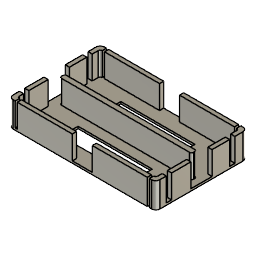
BodyWithArms (Autodesk Fusion 360 archive; units mm, degrees)
design "2SBatteryHolder"
part number: 2025-10-23-18-50-40-159
Autodesk Fusion 360 part; units mm, degrees
(part 1 of 2)
sketch "Sketch1" plane through (0, 0, 0) normal (0, 0, 1) x (1, 0, 0)
  line L0 (-32.7, -18.6) -> (-32.7, 18.6)
  line L1 (32.7, 18.6) -> (32.7, -18.6)
  line L2 (32.7, -19.6) -> (-32.7, 19.6) construction
  line L3 (-32.7, -19.6) -> (32.7, 19.6) construction
  line L4 (-29.9642, -1.4107) -> (30.45, -1.4107)
  line L5 (-29.9642, 0.9987) -> (30.45, 0.9987)
  line L6 (-34.7, -19.6) -> (-34.7, 19.6)
  line L7 (34.7, 19.6) -> (34.7, -19.6)
  arc A0 (-32.7, 21.6) -> (-34.7, 19.6) centre (-32.7, 19.6) ccw
  arc A1 (-34.7, -19.6) -> (-32.7, -21.6) centre (-32.7, -19.6) ccw
  arc A2 (32.7, -21.6) -> (34.7, -19.6) centre (32.7, -19.6) ccw
  arc A3 (34.7, 19.6) -> (32.7, 21.6) centre (32.7, 19.6) ccw
  arc A4 (32.7, 18.6) -> (31.7, 19.6) centre (31.7, 18.6) ccw
  arc A5 (-32.7, -18.6) -> (-31.7, -19.6) centre (-31.7, -18.6) ccw
  arc A6 (-31.7, 19.6) -> (-32.7, 18.6) centre (-31.7, 18.6) ccw
  arc A7 (31.7, -19.6) -> (32.7, -18.6) centre (31.7, -18.6) ccw
  line L8 (-30.9642, 0) -> (-30.95, 0)
  line L9 (-30.9642, -0.0013) -> (-30.9642, -0.4107)
  line L10 (31.45, -0.0013) -> (31.45, -0.4107)
  line L11 (-32.7366, -16.6001) -> (-34.7, -16.6001)
  line L12 (-32.7583, -14.1002) -> (-34.7, -14.1002)
  line L13 (34.6417, -14.1002) -> (32.7, -14.1002)
  line L14 (34.6634, -16.6001) -> (32.7, -16.6001)
  line L15 (-32.7583, 15.7998) -> (-34.7, 15.7998)
  line L16 (-32.7366, 13.2999) -> (-34.7, 13.2999)
  line L17 (34.6417, 15.7998) -> (32.7, 15.7998)
  line L18 (34.6634, 13.2999) -> (32.7, 13.2999)
  arc A8 (31.45, -0.0013) -> (30.45, 0.9987) centre (30.45, -0.0013) ccw
  arc A9 (30.45, -1.4107) -> (31.45, -0.4107) centre (30.45, -0.4107) ccw
  arc A10 (-29.9642, 0.9987) -> (-30.9642, -0.0013) centre (-29.9642, -0.0013) ccw
  arc A11 (-30.9642, -0.4107) -> (-29.9642, -1.4107) centre (-29.9642, -0.4107) ccw
  line L19 (-4.7, -19.6) -> (-4.7, -21.6)
  line L20 (4.7, -19.6) -> (4.7, -21.6)
  line L21 (32.7, -21.6) -> (4.7, -21.6)
  line L22 (-4.7, -21.6) -> (-32.7, -21.6)
  line L23 (31.7, -19.6) -> (4.7, -19.6)
  line L24 (-4.7, -19.6) -> (-31.7, -19.6)
  line L25 (4.7, 19.6) -> (4.7, 21.6)
  line L26 (-4.7, 19.6) -> (-4.7, 21.6)
  line L27 (-32.7, 21.6) -> (-4.7, 21.6)
  line L28 (4.7, 21.6) -> (32.7, 21.6)
  line L29 (-31.7, 19.6) -> (-4.7, 19.6)
  line L30 (4.7, 19.6) -> (31.7, 19.6)
  line L31 (-4.7, -19.6) -> (4.7, -19.6)
  line L32 (-4.7, -21.6) -> (4.7, -21.6)
  line L33 (-4.7, 21.6) -> (4.7, 21.6)
  line L34 (-4.7, 19.6) -> (4.7, 19.6)
  line L35 (17.4965, -6.1) -> (-17.5035, -6.1)
  line L36 (-17.5035, -6.1) -> (-17.5035, -14.1)
  line L37 (-17.5035, -14.1) -> (17.4965, -14.1)
  line L38 (17.4965, -14.1) -> (17.4965, -6.1)
  line L39 (17.4965, -6.1) -> (-17.5035, -14.1) construction
  line L40 (-17.5035, -6.1) -> (17.4965, -14.1) construction
  line L41 (17.4965, 6.1) -> (17.4965, 14.1)
  line L42 (17.4965, 14.1) -> (-17.5035, 6.1) construction
  line L43 (-17.5035, 6.1) -> (17.4965, 6.1)
  line L44 (-17.5035, 14.1) -> (17.4965, 6.1) construction
  line L45 (17.4965, 14.1) -> (-17.5035, 14.1)
  line L46 (-17.5035, 14.1) -> (-17.5035, 6.1)
  line L47 (32.7, 5.0447) -> (34.7, 5.0447)
  line L48 (32.7, -5) -> (34.7, -5)
  line L49 (-34.7, 5.0447) -> (-32.7, 5.0447)
  line L50 (-34.7, -5) -> (-32.7, -5)
  line L51 (-31.7, -19.6) -> (-31.7, -21.6)
  line L52 (-30.7, -19.6) -> (-30.7, -21.6)
  line L53 (-31.7, 19.6) -> (-31.7, 21.6)
  line L54 (-30.7, 21.6) -> (-30.7, 19.6)
  line L55 (31.7, 19.6) -> (31.7, 21.6)
  line L56 (30.7, 19.6) -> (30.7, 21.6)
  line L57 (31.7, -19.6) -> (31.7, -21.6)
  line L58 (31.7, -21.6) -> (30.7, -21.6)
  line L59 (30.7, -21.6) -> (30.7, -19.6)
  line L60 (-32.8064, 13.2999) -> (-32.7, 13.2999)
  line L61 (-32.7715, 15.7998) -> (-32.7, 15.7998)
  line L62 (-32.7583, -14.1002) -> (-32.7, -14.1002)
  line L63 (-34.7, -14.1002) -> (-32.7, -14.1002)
  line L64 (34.5487, -14.1002) -> (34.7, -14.1002)
  line L65 (34.5809, -16.6001) -> (34.7, -16.6001)
  line L66 (34.5908, 13.2999) -> (34.7, 13.2999)
  line L67 (34.5914, 15.7998) -> (34.7, 15.7998)
  line L68 (-34.7, -16.6001) -> (-32.7, -16.6001)
  point P0 (-0.0035, -10.1)
  point P1 (-0.0035, 10.1)
  dimension "d1" = 65.4
  dimension "d2" = 39.2
  dimension "d6" = 2
  dimension "d7" = 1
  dimension "d10" = 5
  dimension "d11" = 2.5
  dimension "d15" = 67.4
  dimension "d16" = 29.9
  dimension "d19" = 1
  dimension "d22" = 30
  dimension "d23" = 30
  dimension "d24" = 30
  dimension "d25" = 30
  dimension "d28" = 35
  dimension "d29" = 8
  dimension "d32" = 0
  dimension "d33" = 20.2
  dimension "d38" = -67.4
  dimension "d39" = 0
  constraint horizontal L23
  constraint perpendicular L0 L23
  constraint parallel L23 L29
  constraint parallel L0 L1
  constraint coincident L2 origin
  constraint coincident L3 origin
  constraint perpendicular L1 L4
  constraint perpendicular L1 L5
  constraint tangent A0 L27
  constraint tangent L6 A0
  constraint tangent A1 L21
  constraint tangent L6 A1
  constraint equal A0 A1
  constraint tangent L7 A2
  constraint tangent A2 L21
  constraint equal A0 A2
  constraint tangent A3 L27
  constraint tangent L7 A3
  constraint equal A0 A3
  constraint coincident L3.end L29
  constraint coincident L3.end L1
  constraint tangent A4 L29
  constraint tangent L1 A4
  constraint coincident L3.start L23
  constraint coincident L3.start L0
  constraint tangent A5 L23
  constraint tangent L0 A5
  constraint equal A4 A5
  constraint coincident L2.end L0
  constraint coincident L2.end L29
  constraint tangent L0 A6
  constraint tangent A6 L29
  constraint equal A4 A6
  constraint coincident L2.start L1
  constraint coincident L2.start L23
  constraint tangent L1 A7
  constraint tangent A7 L23
  constraint equal A4 A7
  constraint perpendicular L4 L9
  constraint coincident L9 L8.start
  constraint perpendicular L4 L10
  constraint coincident L6 L11.end
  constraint perpendicular L6 L11
  constraint coincident L6 L12.end
  constraint perpendicular L6 L12
  constraint tangent L5 A8
  constraint tangent L10 A8
  constraint tangent L4 A9
  constraint tangent L10 A9
  constraint equal A8 A9
  constraint tangent L5 A10
  constraint tangent L9 A10
  constraint equal A8 A10
  constraint tangent L9 A11
  constraint tangent L4 A11
  constraint equal A8 A11
  constraint coincident L19.end L21
  constraint perpendicular L19 L21
  constraint perpendicular L20 L21
  constraint collinear L21 L22
  constraint collinear L23 L24
  constraint coincident L25.end L27
  constraint perpendicular L25 L27
  constraint perpendicular L26 L27
  constraint collinear L27 L28
  constraint collinear L29 L30
  constraint perpendicular L20 L31
  constraint perpendicular L25 L34
  constraint horizontal L35
  constraint perpendicular L35 L36
  constraint parallel L35 L37
  constraint parallel L36 L38
  constraint coincident L39 P0
  constraint coincident L40 P0
  constraint coincident L1 L47.start
  constraint coincident L7 L47.end
  constraint perpendicular L7 L47
  constraint coincident L1 L48.start
  constraint coincident L7 L48.end
  constraint perpendicular L7 L48
  constraint coincident L22 L51.end
  constraint perpendicular L22 L51
  constraint coincident L24 L52.start
  constraint coincident L22 L52.end
  constraint perpendicular L22 L52
  constraint coincident L27 L53.end
  constraint perpendicular L27 L53
  constraint coincident L27 L54.start
  constraint coincident L29 L54.end
  constraint perpendicular L29 L54
  constraint coincident L28 L55.end
  constraint perpendicular L28 L55
  constraint coincident L30 L56.start
  constraint coincident L28 L56.end
  constraint perpendicular L28 L56
  constraint coincident L21 L57.end
  constraint perpendicular L21 L57
  constraint coincident L21 L58.end
  constraint coincident L23 L59.end
  constraint perpendicular L23 L59
  constraint coincident L16 L60.start
  constraint coincident L0 L60.end
  constraint perpendicular L0 L60
  constraint coincident L15 L61.start
  constraint coincident L0 L61.end
  constraint perpendicular L0 L61
  constraint coincident L0 L62.end
  constraint perpendicular L0 L62
  constraint perpendicular L0 L63
  constraint coincident L13 L64.start
  constraint coincident L7 L64.end
  constraint perpendicular L7 L64
  constraint coincident L14 L65.start
  constraint coincident L7 L65.end
  constraint perpendicular L7 L65
  constraint coincident L18 L66.start
  constraint coincident L7 L66.end
  constraint perpendicular L7 L66
  constraint coincident L17 L67.start
  constraint coincident L7 L67.end
  constraint perpendicular L7 L67
  constraint coincident L0 L68.end
  constraint perpendicular L0 L68
  measures "d1" distance of L2.end L3.end
  measures "d2" distance of L3.start L2.end
  measures "d6" radius of A0
  measures "d7" radius of A4
  measures "d10" distance of A1.end L11.start
  measures "d11" distance of L11.start L12.start
  measures "d19" radius of A8
  measures "d22" distance of L6.start L19.start
  measures "d23" distance of L7.end L20.start
  measures "d24" distance of L7.start L25.start
  measures "d25" distance of L6.end L26.start
  measures "d28" distance of L36.end L37.end
  measures "d29" distance of L35.end L36.end
extrude "Extrude1" add sketch "Sketch1" along normal blind 1 contours L0 L1 A4 A5 A6 A7 L23 L24 L29 L30 L31 L34 | L0 L6 L11 L12 L62 L63 L68 | L22 L24 L51 L52 | L0 L6 L49 L50 | L19 L20 L31 L32 | L0 L6 L15 L16 L60 L61 | L27 L29 L53 L54 | L1 L7 L13 L14 L64 L65 | L25 L26 L33 L34 | L1 L7 L47 L48 | L1 L7 L17 L18 L66 L67
extrude "Extrude2" add sketch "Sketch1" along normal blind 12 contours L0 L6 A1 A5 L11 L22 L51 L68 | L0 L6 L12 L50 L62 L63 | L19 L22 L24 L52 | L0 L6 L16 L49 L60 | L20 L21 L23 L59 | L0 L6 A0 A6 L15 L27 L53 L61 | L1 L7 A2 A7 L14 L21 L57 L65 | L26 L27 L29 L54 | L1 L7 L13 L48 L64 | L25 L28 L30 L56 | L1 L7 L18 L47 L66 | L1 L7 A3 A4 L17 L28 L55 L67 | L4 L5 L9 L10 A8 A9 A10 A11

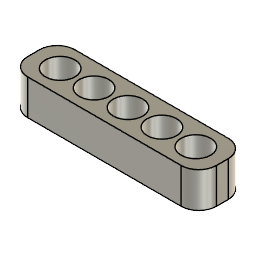
design "LedIndicator"
part number: 2025-10-29-04-20-47-498
Autodesk Fusion 360 part; units mm, degrees
sketch "Sketch1" plane through (0, 0, 0) normal (0, 0, 1) x (1, 0, 0)
  line L0 (13, 4) -> (-13, 4)
  line L1 (-16, 1) -> (-16, -1)
  line L2 (-13, -4) -> (13, -4)
  line L3 (16, -1) -> (16, 1)
  line L4 (16, 4) -> (-16, -4) construction
  line L5 (-16, 4) -> (16, -4) construction
  arc A0 (-13, 4) -> (-16, 1) centre (-13, 1) ccw
  arc A1 (-16, -1) -> (-13, -4) centre (-13, -1) ccw
  arc A2 (16, 1) -> (13, 4) centre (13, 1) ccw
  arc A3 (13, -4) -> (16, -1) centre (13, -1) ccw
  circle A4 centre (-11.5, -0.0004) radius 2.5
  circle A5 centre (-5.75, -0.0004) radius 2.5
  circle A6 centre (0, -0.0004) radius 2.5
  circle A7 centre (5.75, -0.0004) radius 2.5
  circle A8 centre (11.5, -0.0004) radius 2.5
  line L6 (-8.3524, 2.9996) -> (-8.8524, 2.9996)
  line L7 (-8.8524, 2.9996) -> (-8.8524, -3.0004)
  line L8 (-8.8524, -3.0004) -> (-8.3524, -3.0004)
  line L9 (-8.3524, -3.0004) -> (-8.3524, 2.9996)
  line L10 (-8.3524, 2.9996) -> (-8.8524, -3.0004) construction
  line L11 (-8.8524, 2.9996) -> (-8.3524, -3.0004) construction
  line L12 (-3.1024, 2.9996) -> (-2.6024, -3.0004) construction
  line L13 (-3.1024, 2.9996) -> (-3.1024, -3.0004)
  line L14 (-2.6024, 2.9996) -> (-3.1024, -3.0004) construction
  line L15 (-2.6024, -3.0004) -> (-2.6024, 2.9996)
  line L16 (2.6476, 2.9996) -> (3.1476, -3.0004) construction
  line L17 (2.6476, 2.9996) -> (2.6476, -3.0004)
  line L18 (3.1476, 2.9996) -> (2.6476, -3.0004) construction
  line L19 (3.1476, -3.0004) -> (3.1476, 2.9996)
  line L20 (8.3976, 2.9996) -> (8.8976, -3.0004) construction
  line L21 (8.3976, 2.9996) -> (8.3976, -3.0004)
  line L22 (8.8976, 2.9996) -> (8.3976, -3.0004) construction
  line L23 (8.8976, -3.0004) -> (8.8976, 2.9996)
  line L24 (8.3976, 2.9996) -> (8.8976, 2.9996)
  line L25 (8.3976, -3.0004) -> (8.8976, -3.0004)
  line L26 (2.6476, -3.0004) -> (3.1476, -3.0004)
  line L27 (2.6476, 2.9996) -> (3.1476, 2.9996)
  line L28 (-3.1024, 2.9996) -> (-2.6024, 2.9996)
  line L29 (-3.1024, -3.0004) -> (-2.6024, -3.0004)
  line L30 (15, -1) -> (15, 1)
  arc A9 (15, 1) -> (13, 3) centre (13, 1) ccw
  line L31 (13, 3) -> (-13, 3)
  arc A10 (-13, 3) -> (-15, 1) centre (-13, 1) ccw
  line L32 (-15, 1) -> (-15, -1)
  arc A11 (-15, -1) -> (-13, -3) centre (-13, -1) ccw
  line L33 (-13, -3) -> (13, -3)
  arc A12 (13, -3) -> (15, -1) centre (13, -1) ccw
  line L34 (-15.5, 1) -> (-15, 1)
  line L35 (-15.5, 1) -> (-16, 1)
  line L36 (-15.5, 2) -> (-14.7321, 2)
  line L37 (-15.5, 2) -> (-15.8284, 2)
  line L38 (-15, -1) -> (-16, -1)
  line L39 (-15.8284, -2) -> (-14.7321, -2)
  point P0 (-8.6024, -0.0004)
  dimension "d1" = 32
  dimension "d2" = 8
  dimension "d3" = 3
  dimension "d7" = 5
  dimension "d10" = 23
  dimension "d11" = 0
  dimension "d12" = 0.5
  dimension "d13" = 6
  dimension "d16" = 17.25
  dimension "d17" = 0
  dimension "d22" = -1
  dimension "d31" = 2
  constraint horizontal L0
  constraint perpendicular L0 L1
  constraint parallel L0 L2
  constraint parallel L1 L3
  constraint coincident L4 origin
  constraint coincident L5 origin
  constraint coincident L5.start L0
  constraint coincident L5.start L1
  constraint tangent L0 A0
  constraint tangent L1 A0
  constraint coincident L4.end L2
  constraint coincident L4.end L1
  constraint tangent L2 A1
  constraint tangent L1 A1
  constraint equal A0 A1
  constraint coincident L4.start L0
  constraint coincident L4.start L3
  constraint tangent L0 A2
  constraint tangent L3 A2
  constraint equal A0 A2
  constraint coincident L5.end L2
  constraint coincident L5.end L3
  constraint tangent L2 A3
  constraint tangent L3 A3
  constraint equal A0 A3
  constraint horizontal L6
  constraint perpendicular L6 L7
  constraint parallel L6 L8
  constraint parallel L7 L9
  constraint coincident L10 P0
  constraint coincident L11 P0
  constraint coincident A10 L36.end
  constraint coincident A0 L37.end
  constraint perpendicular L1 L38
  constraint coincident A1 L39.start
  constraint coincident A11 L39.end
  measures "d1" distance of L4.end L5.end
  measures "d2" distance of L5.start L4.end
  measures "d3" radius of A0
  measures "d7" diameter of A4
  measures "d12" distance of L7.end L8.end
  measures "d13" distance of L6.end L7.end
  measures "d31" distance of A10.end L32.end
extrude "Extrude1" add sketch "Sketch1" along normal blind 6 contours L0 L2 L3 A0 A1 A2 A3 L6 L8 L24 L25 L26 L27 L28 L29 L30 A9 L31 A10 A11 L33 A12 L36 L37 L39 | A0 A10 L34 L35 L36 L37 | L1 L32 L34 L35 L38 | A1 A11 L38 L39 | L7 L31 A10 L32 A11 L33 | L6 L7 L8 L9 L31 L33 | L9 L13 L31 L33 | L13 L15 L28 L29 L31 L33 | L15 L17 L31 L33 | L17 L19 L26 L27 L31 L33 | L19 L21 L31 L33 | L21 L23 L24 L25 L31 L33 | L23 L30 A9 L31 L33 A12 | A4 | A5 | A6 | A7 | A8
extrude "Extrude3" cut sketch "Sketch1" along normal blind 6 contours A4 | A5 | A6 | A7 | A8
extrude "Extrude4" cut sketch "Sketch1" along normal blind 2.5 contours L6 L7 L9 L13 L15 L17 L19 L21 L23 L24 L27 L28 L30 A9 L31 A10 L32 A11 L33 A12
extrude "Extrude5" cut sketch "Sketch1" along normal blind 1 contours L6 L7 L8 L9 L31 L33 | L13 L15 L28 L29 L31 L33 | L17 L19 L26 L27 L31 L33 | L21 L23 L24 L25 L31 L33
extrude "Extrude6" cut sketch "Sketch1" along normal blind 2.5 contours A0 A10 L34 L35 L36 L37 | A1 A11 L38 L39
extrude "Extrude7" add sketch "Sketch1" along normal blind 1 contours A0 A10 L34 L35 L36 L37 | A1 A11 L38 L39

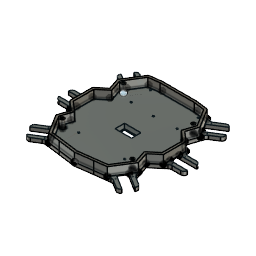
design "MiddlePlateV2"
part number: 2025-11-01-04-09-30-554
Autodesk Fusion 360 part; units mm, degrees
sketch "Sketch1" plane through (0, 0, 0) normal (0, 0, 1) x (1, 0, 0)
  line L0 (-80, -41.1763) -> (-36.8632, -110)
  line L1 (-36.9537, 110) -> (-80, 41.1666)
  line L2 (36.9063, 110) -> (80, 41.1773)
  line L3 (36.9063, -110) -> (80, -41.1763)
  line L4 (-80, 41.1666) -> (-80, -41.1763)
  line L5 (80, -41.1763) -> (80, 41.1773)
  line L6 (-36.9537, 110) -> (36.9063, 110)
  line L7 (-80, 41.1666) -> (-67.7518, 60.7521)
  line L8 (-36.9537, 110) -> (-49.2019, 90.4145)
  line L9 (-49.2019, 90.4145) -> (-53.2528, 83.9369)
  line L10 (-67.7518, 60.7521) -> (-63.7009, 67.2297)
  circle A0 centre (-75.6456, 102.4461) radius 0.8
  circle A1 centre (-90.1447, 79.2614) radius 0.8
  line L11 (-90.3545, 72.1906) -> (-80, 41.1666)
  line L12 (-69.38, 105.7298) -> (-36.9537, 110)
  arc A2 (-90.3545, 72.1906) -> (-94.5378, 77.5033) centre (-99.8401, 69.0247) ccw
  line L13 (-94.5378, 77.5033) -> (-67.7518, 60.7521)
  arc A3 (-75.9879, 107.1657) -> (-69.38, 105.7298) centre (-70.6856, 115.6442) ccw
  line L14 (-75.9879, 107.1657) -> (-49.2019, 90.4145)
  line L15 (0.0216, -110) -> (0.0216, -115)
  line L16 (0.0216, -115) -> (-36.8632, -110)
  line L17 (36.9063, -110) -> (0.0216, -115)
  point P0 (-116.2069, 91.0544)
  point P1 (-97.6569, 120.7168)
  dimension "d4" = 23.1
  dimension "d5" = 23.1
  dimension "d6" = 7.64
  dimension "d7" = 7.64
  dimension "d8" = 57.15
  dimension "d10" = 57.15
  dimension "d13" = 1.6
  dimension "d15" = 1.6
  dimension "d17" = 10
  dimension "d18" = 10
  constraint vertical L4
  constraint perpendicular L5 L6
  constraint parallel L1 L7
  constraint parallel L1 L8
  constraint parallel L1 L9
  constraint coincident L1 L10.end
  constraint tangent L11 A2
  constraint tangent L12 A3
  measures "d4" distance of L1.end L7.end
  measures "d5" distance of L1.start L8.end
  measures "d6" distance of L8.end L9.end
  measures "d7" distance of L7.end L10.end
  measures "d8" distance of L7.end P0
  measures "d10" distance of L8.end P1
  measures "d13" diameter of A0
  measures "d15" diameter of A1
  measures "d17" radius of A2
  measures "d18" radius of A3
sketch "Sketch2" plane through (0, 0, 0) normal (0, 0, 1) x (1, 0, 0)
  line L0 (-36.9537, 110) -> (36.9063, 110)
  line L1 (-36.9537, 110) -> (-80, 41.1666)
  line L2 (-80, 41.1666) -> (-80, -41.1763)
  line L3 (-80, -41.1763) -> (-36.8632, -110)
  line L4 (36.9063, -110) -> (80, -41.1763)
  line L5 (80, -41.1763) -> (80, 41.1773)
  line L6 (36.9063, 110) -> (80, 41.1773)
  line L7 (-90.3545, 72.1906) -> (-80, 41.1666)
  arc A0 (-90.3545, 72.1906) -> (-94.5378, 77.5033) centre (-99.8401, 69.0247) ccw
  line L8 (-94.5378, 77.5033) -> (-110.2719, 87.3429)
  line L9 (-94.5378, 77.5033) -> (-67.7518, 60.7521)
  line L10 (-63.7009, 67.2297) -> (-112.156, 97.5321)
  circle A1 centre (-90.1447, 79.2614) radius 0.8
  arc A2 (-112.4953, 96.9894) -> (-110.2719, 87.3429) centre (-106.5603, 93.2779) ccw
  line L11 (-112.4953, 96.9894) -> (-112.156, 97.5321)
  arc A3 (-91.7219, 117.0052) -> (-101.3685, 114.7818) centre (-95.4335, 111.0702) ccw
  line L12 (-101.7078, 114.2392) -> (-101.3685, 114.7818)
  line L13 (-53.2528, 83.9369) -> (-101.7078, 114.2392)
  line L14 (-75.9879, 107.1657) -> (-91.7219, 117.0052)
  line L15 (-75.9879, 107.1657) -> (-49.2019, 90.4145)
  circle A4 centre (-75.6456, 102.4461) radius 0.8
  line L16 (-69.38, 105.7298) -> (-36.9537, 110)
  arc A5 (-75.9879, 107.1657) -> (-69.38, 105.7298) centre (-70.6856, 115.6442) ccw
  line L17 (-32.7981, 102.5) -> (-72.5, 39.0146)
  line L18 (-72.5, 39.0146) -> (-72.5, -39.0202)
  line L19 (-72.5, -39.0202) -> (-32.7126, -102.5)
  line L20 (32.7535, -102.5) -> (72.5, -39.022)
  line L21 (72.5, -39.022) -> (72.5, 39.0229)
  line L22 (32.7535, 102.5) -> (72.5, 39.0229)
  line L23 (-32.7981, 102.5) -> (32.7535, 102.5)
  line L24 (-80, -0.0049) -> (-80, -41.1763)
  line L25 (-80, -0.0049) -> (-80, -9.8574)
  line L26 (-80, -0.0049) -> (-80, 9.8476)
  line L27 (-80, -9.8574) -> (-137.15, -9.8574)
  line L28 (-80, 9.8476) -> (-137.15, 9.8476)
  line L29 (-130.1576, -17.5027) -> (-111.6546, -17.5166)
  line L30 (-80, 9.8476) -> (-80, 17.4876)
  line L31 (-111.641, 17.2169) -> (-130.2039, 17.0581)
  line L32 (-137.1425, 10.2052) -> (-137.15, 9.8476)
  line L33 (-137.1523, -10.4764) -> (-137.15, -9.8574)
  circle A6 centre (-108.8, -13.7676) radius 0.8
  circle A7 centre (-108.8, 13.6676) radius 0.8
  line L34 (-105.2314, 19.6131) -> (-80, 41.1666)
  line L35 (-105.2084, -19.878) -> (-80, -41.1763)
  arc A8 (-111.641, 17.2169) -> (-105.2314, 19.6131) centre (-111.7266, 27.2166) ccw
  arc A9 (-105.2084, -19.878) -> (-111.6546, -17.5166) centre (-111.6622, -27.5166) ccw
  line L36 (-111.641, 17.2169) -> (-80, 17.2169)
  line L37 (-111.6546, -17.5166) -> (-79.9958, -17.5166)
  arc A10 (-137.1523, -10.4764) -> (-130.1576, -17.5027) centre (-130.1524, -10.5027) ccw
  arc A11 (-130.2039, 17.0581) -> (-137.1425, 10.2052) centre (-130.144, 10.0584) ccw
  line L38 (111.6592, -17.5166) -> (130.0116, -17.5166)
  line L39 (111.6628, 17.4876) -> (130.0112, 17.4876)
  line L40 (137, 9.8476) -> (137.0099, 10.3502)
  line L41 (137, -9.8574) -> (137.0102, -10.3795)
  line L42 (80, -9.8574) -> (137, -9.8574)
  line L43 (80, 9.8476) -> (137, 9.8476)
  line L44 (80, -17.5166) -> (80, -9.8574)
  line L45 (80, 9.8476) -> (80, 17.4876)
  circle A12 centre (108.8, -13.685) radius 0.8
  circle A13 centre (108.8, 13.6621) radius 0.8
  line L46 (80, -41.1763) -> (105.205, -19.8783)
  line L47 (105.2038, 19.8534) -> (80, 41.1773)
  line L48 (49.1699, 90.4145) -> (53.2259, 83.9369)
  line L49 (63.6871, 67.2297) -> (67.7431, 60.7521)
  line L50 (75.9473, 107.1813) -> (91.6749, 117.0292)
  line L51 (53.2259, 83.9369) -> (101.6638, 114.2665)
  line L52 (101.3228, 114.8112) -> (101.6638, 114.2665)
  line L53 (63.6871, 67.2297) -> (112.1251, 97.5594)
  line L54 (94.5192, 77.5181) -> (110.2482, 87.3668)
  line L55 (112.1251, 97.5594) -> (112.4661, 97.0147)
  line L56 (90.3391, 72.2039) -> (80, 41.1773)
  line L57 (69.3385, 105.7419) -> (36.9063, 110)
  circle A14 centre (75.6076, 102.4599) radius 0.8
  circle A15 centre (90.1248, 79.2752) radius 0.8
  arc A16 (110.2482, 87.3668) -> (112.4661, 97.0147) centre (106.5332, 93.2997) ccw
  arc A17 (101.3228, 114.8112) -> (91.6749, 117.0292) centre (95.3898, 111.0963) ccw
  arc A18 (69.3385, 105.7419) -> (75.9473, 107.1813) centre (70.6403, 115.6569) ccw
  arc A19 (94.5192, 77.5181) -> (90.3391, 72.2039) centre (99.8263, 69.0425) ccw
  arc A20 (105.2038, 19.8534) -> (111.6628, 17.4876) centre (111.6628, 27.4876) ccw
  arc A21 (111.6592, -17.5166) -> (105.205, -19.8783) centre (111.6592, -27.5166) ccw
  arc A22 (137.0099, 10.3502) -> (130.0112, 17.4876) centre (130.0112, 10.4876) ccw
  arc A23 (130.0116, -17.5166) -> (137.0102, -10.3795) centre (130.0116, -10.5166) ccw
  line L58 (94.5192, 77.5181) -> (67.7431, 60.7521)
  line L59 (75.9473, 107.1813) -> (49.1699, 90.4145)
  line L60 (111.6628, 17.4876) -> (80, 17.4876)
  line L61 (111.6592, -17.5166) -> (80, -17.5166)
  line L62 (-36.8632, -110) -> (-49.1311, -90.4269)
  line L63 (-49.1311, -90.4269) -> (-53.1886, -83.9533)
  line L64 (-75.9002, -107.205) -> (-91.6243, -117.0604)
  line L65 (-53.1886, -83.9533) -> (-101.613, -114.3045)
  line L66 (-101.2732, -114.8467) -> (-101.613, -114.3045)
  line L67 (-53.1886, -83.9533) -> (-63.6535, -67.2568)
  line L68 (-63.6535, -67.2568) -> (-67.7109, -60.7833)
  line L69 (-63.6535, -67.2568) -> (-112.0779, -97.608)
  line L70 (-94.4841, -77.564) -> (-110.2041, -87.4169)
  line L71 (-112.4178, -97.0657) -> (-112.0779, -97.608)
  circle A24 centre (-75.5627, -102.4851) radius 0.8
  circle A25 centre (-90.0352, -79.3859) radius 0.8
  line L72 (-69.2938, -105.7625) -> (-36.8632, -110)
  line L73 (-90.3034, -72.239) -> (-80, -41.1763)
  arc A26 (-69.2938, -105.7625) -> (-75.9002, -107.205) centre (-70.5895, -115.6782) ccw
  arc A27 (-94.4841, -77.564) -> (-90.3034, -72.239) centre (-99.7949, -69.0907) ccw
  arc A28 (-101.2732, -114.8467) -> (-91.6243, -117.0604) centre (-95.3419, -111.1292) ccw
  arc A29 (-110.2041, -87.4169) -> (-112.4178, -97.0657) centre (-106.4866, -93.3481) ccw
  line L74 (67.7232, -60.7833) -> (63.6698, -67.2568)
  line L75 (53.2154, -83.9533) -> (49.162, -90.4269)
  line L76 (94.5032, -77.5515) -> (110.2284, -87.3977)
  line L77 (63.6698, -67.2568) -> (112.1079, -97.5862)
  line L78 (112.4464, -97.0456) -> (112.1079, -97.5862)
  line L79 (53.2154, -83.9533) -> (101.6535, -114.2827)
  line L80 (75.938, -107.1925) -> (91.6672, -117.0413)
  line L81 (101.315, -114.8233) -> (101.6535, -114.2827)
  circle A30 centre (90.0549, -79.3769) radius 0.8
  circle A31 centre (75.5436, -102.5512) radius 0.8
  line L82 (80, -41.1763) -> (90.3206, -72.2298)
  line L83 (69.3323, -105.7528) -> (36.9063, -110)
  arc A32 (90.3206, -72.2298) -> (94.5032, -77.5515) centre (99.8102, -69.0759) ccw
  arc A33 (75.938, -107.1925) -> (69.3323, -105.7528) centre (70.631, -115.6682) ccw
  arc A34 (112.4464, -97.0456) -> (110.2284, -87.3977) centre (106.5135, -93.3307) ccw
  arc A35 (91.6672, -117.0413) -> (101.315, -114.8233) centre (95.3821, -111.1084) ccw
  line L84 (94.5032, -77.5515) -> (67.7232, -60.7833)
  line L85 (75.938, -107.1925) -> (49.162, -90.4269)
  line L86 (-94.4841, -77.564) -> (-67.7109, -60.7833)
  line L87 (-75.9002, -107.205) -> (-49.1311, -90.4269)
  line L88 (-36.8632, -110) -> (0.0216, -115)
  line L89 (36.9063, -110) -> (-0.5132, -114.9275)
  line L90 (-32.7126, -102.5) -> (0.0205, -107.5)
  line L91 (0.0205, -107.5) -> (32.7535, -102.5)
  circle A36 centre (-51.1048, -99.1541) radius 1.85
  circle A37 centre (51.1462, 99.1427) radius 1.85
  circle A38 centre (-51.1844, 99.1397) radius 1.85
  circle A39 centre (51.1406, -99.1516) radius 1.85
  line L92 (-32.7981, 102.5) -> (-27.7981, 102.5) construction
  circle A40 centre (-0.0053, 54.0187) radius 1.85
  circle A41 centre (0.0205, -99.5) radius 1.85
  circle A42 centre (0.0205, -99.5) radius 4.85
  circle A43 centre (-0.0053, 54.0187) radius 4.85
  line L93 (-0.0053, 54.0187) -> (2.0172, 54.0194)
  point P0 (137.15, -17.5166)
  point P1 (137.15, 17.4876)
  point P2 (97.6078, 120.7441)
  point P3 (116.1811, 91.0818)
  point P4 (-97.5556, -120.778)
  point P5 (-116.1354, -91.1344)
  point P6 (116.1613, -91.1126)
  point P7 (97.6001, -120.7562)
  dimension "d19" = -7.5
  dimension "d30" = 9.8525
  dimension "d31" = 9.8525
  dimension "d32" = 57.15
  dimension "d33" = 57.15
  dimension "d35" = 7.64
  dimension "d38" = 1.6
  dimension "d39" = 1.6
  dimension "d40" = 10
  dimension "d41" = 180
  dimension "d42" = 7
  dimension "d43" = 57.15
  dimension "d44" = 57.15
  dimension "d48" = 1.6
  dimension "d49" = 1.6
  dimension "d54" = 57.15
  dimension "d55" = 57.15
  dimension "d56" = 57.15
  dimension "d57" = 57.15
  dimension "d60" = 1.6
  dimension "d61" = 1.6
  dimension "d62" = 7
  dimension "d63" = 10
  dimension "d64" = 7
  dimension "d65" = 23.1
  dimension "d66" = 7.64
  dimension "d67" = 57.15
  dimension "d68" = 57.15
  dimension "d69" = 19.705
  dimension "d70" = 7.64
  dimension "d71" = 57.15
  dimension "d72" = 57.15
  dimension "d75" = 1.6
  dimension "d76" = 1.6
  dimension "d77" = 10
  dimension "d78" = 7
  dimension "d79" = 57.15
  dimension "d80" = 57.15
  dimension "d81" = 57.15
  dimension "d82" = 57.15
  dimension "d85" = 1.6
  dimension "d86" = 1.6
  dimension "d87" = 10
  dimension "d88" = 7
  dimension "d232" = 3.7
  dimension "d233" = 3.7
  dimension "d234" = 3.7
  dimension "d235" = 3.7
  dimension "d236" = 8
  dimension "d242" = 3.7
  dimension "d244" = 3.7
  dimension "d245" = 3
  dimension "d247" = 3
  constraint midpoint L2 L24.start
  constraint parallel L24 L25
  constraint parallel L2 L26
  constraint perpendicular L25 L27
  constraint perpendicular L26 L28
  constraint perpendicular L28 L30
  constraint coincident L30.end L31
  constraint tangent L34 A8
  constraint tangent L31 A8
  constraint tangent L35 A9
  constraint tangent L29 A9
  constraint equal A8 A9
  constraint horizontal L36
  constraint coincident L30 L36.end
  constraint perpendicular L24 L37
  constraint tangent L29 A10
  constraint tangent L33 A10
  constraint tangent L32 A11
  constraint tangent L31 A11
  constraint equal A10 A11
  constraint coincident L5 L44.start
  constraint coincident L5 L45.end
  constraint perpendicular L5 L38
  constraint perpendicular L5 L39
  constraint coincident L5 L42.start
  constraint coincident L5 L43.start
  constraint perpendicular L42 L44
  constraint coincident L6 L48.start
  constraint coincident L6 L49.start
  constraint coincident L6 L49.end
  constraint coincident L6 L48.end
  constraint perpendicular L6 L50
  constraint perpendicular L48 L51
  constraint perpendicular L6 L53
  constraint perpendicular L49 L54
  constraint coincident P3 L55
  constraint coincident P3 L54
  constraint tangent L55 A16
  constraint tangent L54 A16
  constraint coincident P2 L52
  constraint coincident P2 L50
  constraint tangent L52 A17
  constraint tangent L50 A17
  constraint equal A16 A17
  constraint coincident L48.start L50
  constraint tangent L50 A18
  constraint tangent L57 A18
  constraint coincident L49.end L54
  constraint tangent L54 A19
  constraint tangent L56 A19
  constraint equal A18 A19
  constraint coincident L45.end L39
  constraint tangent L39 A20
  constraint tangent L47 A20
  constraint equal A18 A20
  constraint coincident L44.start L38
  constraint tangent L38 A21
  constraint tangent L46 A21
  constraint equal A18 A21
  constraint coincident P1 L39
  constraint coincident P1 L40
  constraint tangent L39 A22
  constraint tangent L40 A22
  constraint coincident P0 L41
  constraint coincident P0 L38
  constraint tangent L41 A23
  constraint tangent L38 A23
  constraint equal A22 A23
  constraint parallel L3 L62
  constraint parallel L3 L63
  constraint perpendicular L3 L64
  constraint perpendicular L3 L65
  constraint coincident L3 L67.end
  constraint perpendicular L65 L68
  constraint perpendicular L68 L69
  constraint perpendicular L68 L70
  constraint coincident L62.end L64
  constraint tangent L72 A26
  constraint tangent L64 A26
  constraint coincident L68.end L70
  constraint tangent L70 A27
  constraint tangent L73 A27
  constraint equal A26 A27
  constraint coincident P4 L66
  constraint coincident P4 L64
  constraint tangent L66 A28
  constraint tangent L64 A28
  constraint coincident P5 L71
  constraint coincident P5 L70
  constraint tangent L71 A29
  constraint tangent L70 A29
  constraint equal A28 A29
  constraint coincident L4 L75.end
  constraint coincident L4 L75.start
  constraint coincident L4 L74.end
  constraint coincident L4 L74.start
  constraint perpendicular L20 L76
  constraint perpendicular L74 L77
  constraint perpendicular L75 L79
  constraint perpendicular L75 L80
  constraint coincident L74.start L76
  constraint tangent L82 A32
  constraint tangent L76 A32
  constraint coincident L75.end L80
  constraint tangent L80 A33
  constraint tangent L83 A33
  constraint equal A32 A33
  constraint coincident P6 L76
  constraint coincident P6 L78
  constraint tangent L76 A34
  constraint tangent L78 A34
  constraint coincident P7 L81
  constraint coincident P7 L80
  constraint tangent L81 A35
  constraint tangent L80 A35
  constraint equal A34 A35
  constraint coincident L88 L89.end
  constraint horizontal L92
  constraint coincident A40.centre A43.centre
  measures "d30" distance of L24.start L25.end
  measures "d31" distance of L24.start L26.end
  measures "d32" distance of L25.end L27.end
  measures "d33" distance of L26.end L28.end
  measures "d35" distance of L26.end L30.end
  measures "d38" diameter of A6
  measures "d39" diameter of A7
  measures "d40" radius of A8
  measures "d41" angle of L36 L37
  measures "d42" radius of A10
  measures "d43" distance of L44.start P0
  measures "d44" distance of L45.end P1
  measures "d48" diameter of A12
  measures "d49" diameter of A13
  measures "d54" distance of L48.start P2
  measures "d55" distance of L48.end L51.end
  measures "d56" distance of L49.start L53.end
  measures "d57" distance of L49.end P3
  measures "d60" diameter of A14
  measures "d61" diameter of A15
  measures "d62" radius of A16
  measures "d63" radius of A18
  measures "d64" radius of A22
  measures "d65" distance of L3.end L62.end
  measures "d66" distance of L62.end L63.end
  measures "d67" distance of L62.end P4
  measures "d68" distance of L63.end L65.end
  measures "d69" distance of L63.end L67.end
  measures "d70" distance of L67.end L68.end
  measures "d71" distance of L67.end L69.end
  measures "d72" distance of L68.end P5
  measures "d75" diameter of A24
  measures "d76" diameter of A25
  measures "d77" radius of A26
  measures "d78" radius of A28
  measures "d79" distance of L74.start P6
  measures "d80" distance of L74.end L77.end
  measures "d81" distance of L75.start L79.end
  measures "d82" distance of L75.end P7
  measures "d85" diameter of A30
  measures "d86" diameter of A31
  measures "d87" radius of A32
  measures "d88" radius of A34
  measures "d232" diameter of A36
  measures "d233" diameter of A37
  measures "d234" diameter of A38
  measures "d235" diameter of A39
  measures "d236" distance of L90.end A41.centre
  measures "d242" diameter of A40
  measures "d244" diameter of A41
extrude "Extrude1" add sketch "Sketch2" along normal blind 5 contours L17 L18 L19 L20 L21 L22 L23 L90 L91 | A36 | A37 | A38 | A39 | A40 | A41 makes body 1 at (-24.4032, -28.1672, 0) makes body 2 at (1.8133, -99.0435, 3.3333) makes body 3 at (1.8424, 53.9265, 3.3333) makes body 4 at (52.9389, 99.5992, 3.3333) makes body 5 at (-49.312, -98.6976, 3.3333) makes body 6 at (-49.3916, 99.5962, 3.3333) makes body 7 at (52.9334, -98.6951, 3.3333)
extrude "Extrude4" add sketch "Sketch2" along normal blind 5.9 bodies 1 4 5 6 7 2 3
extrude "Extrude30" cut 6 faces at (-0.2511, 53.171, 5) (-0.2048, -98.926, 5) (-51.4097, 99.7137, 5) (50.9209, 99.7168, 5) (50.9154, -98.5776, 5) (-51.3301, -98.58, 5) along direction (0, 0, -1) blind 12 on bodies 1 bodies 1
extrude "Extrude31" add 2 faces at (3.8455, -99.8329, 5.9) (3.8198, 53.6859, 5.9) along direction (0, 0, 1) blind 6 on bodies 1 bodies 1
extrude "Extrude32" cut 2 faces at (3.8198, 53.6859, 11.9) (3.8455, -99.8329, 11.9) along direction (0, 0, -1) blind 4 on bodies 1 bodies 1
chamfer "Chamfer9" distance 0.5 angle 45 6 edges at (-52.8296, -98.4851, 5.9) (49.4158, -98.4826, 5.9) (49.4213, 99.8117, 5.9) (-52.9092, 99.8087, 5.9) (-1.7043, -100.169, 7.9) (-1.7301, 53.3497, 7.9) on bodies 1
sketch "Sketch22" plane through (0, 0, 0) normal (0, 0, -1) x (1, 0, 0)
  circle A0 centre (75.5436, 102.5512) radius 0.8
  circle A1 centre (-75.6456, -102.4461) radius 0.8
  circle A2 centre (108.8, -13.6621) radius 0.8
  circle A3 centre (90.1248, -79.2752) radius 0.8
  circle A4 centre (-90.1447, -79.2614) radius 0.8
  circle A5 centre (-108.8, -13.6676) radius 0.8
  circle A6 centre (-108.8, 13.7676) radius 0.8
  circle A7 centre (-90.0352, 79.3859) radius 0.8
  circle A8 centre (108.8, 13.685) radius 0.8
  circle A9 centre (90.0549, 79.3769) radius 0.8
  circle A10 centre (75.6076, -102.4599) radius 0.8
  circle A11 centre (-75.5627, 102.4851) radius 0.8
  line L0 (-36.8632, 110) -> (-69.2938, 105.7625)
  arc A12 (-75.9002, 107.205) -> (-69.2938, 105.7625) centre (-70.5895, 115.6782) ccw
  line L1 (-75.9002, 107.205) -> (-91.6243, 117.0604)
  arc A13 (-91.6243, 117.0604) -> (-101.2732, 114.8467) centre (-95.3419, 111.1292) ccw
  line L2 (-101.2732, 114.8467) -> (-101.613, 114.3045)
  line L3 (-101.613, 114.3045) -> (-53.1886, 83.9533)
  line L4 (-63.6535, 67.2568) -> (-112.0779, 97.608)
  line L5 (-112.0779, 97.608) -> (-112.4178, 97.0657)
  arc A14 (-112.4178, 97.0657) -> (-110.2041, 87.4169) centre (-106.4866, 93.3481) ccw
  line L6 (-110.2041, 87.4169) -> (-94.4841, 77.564)
  arc A15 (-90.3034, 72.239) -> (-94.4841, 77.564) centre (-99.7949, 69.0907) ccw
  line L7 (-90.3034, 72.239) -> (-80, 41.1763)
  line L8 (-80, 41.1763) -> (-105.2084, 19.878)
  arc A16 (-111.6546, 17.5166) -> (-105.2084, 19.878) centre (-111.6622, 27.5166) ccw
  line L9 (-111.6546, 17.5166) -> (-130.1576, 17.5027)
  arc A17 (-130.1576, 17.5027) -> (-137.1523, 10.4764) centre (-130.1524, 10.5027) ccw
  line L10 (-137.1523, 10.4764) -> (-137.15, 9.8574)
  line L11 (-137.15, 9.8574) -> (-80, 9.8574)
  line L12 (-80, -9.8476) -> (-137.15, -9.8476)
  line L13 (-137.15, -9.8476) -> (-137.1425, -10.2052)
  arc A18 (-137.1425, -10.2052) -> (-130.2039, -17.0581) centre (-130.144, -10.0584) ccw
  line L14 (-130.2039, -17.0581) -> (-111.641, -17.2169)
  arc A19 (-105.2314, -19.6131) -> (-111.641, -17.2169) centre (-111.7266, -27.2166) ccw
  line L15 (-105.2314, -19.6131) -> (-80, -41.1666)
  line L16 (-80, -41.1666) -> (-90.3545, -72.1906)
  arc A20 (-94.5378, -77.5033) -> (-90.3545, -72.1906) centre (-99.8401, -69.0247) ccw
  line L17 (-94.5378, -77.5033) -> (-110.2719, -87.3429)
  arc A21 (-110.2719, -87.3429) -> (-112.4953, -96.9894) centre (-106.5603, -93.2779) ccw
  line L18 (-112.4953, -96.9894) -> (-112.156, -97.5321)
  line L19 (-112.156, -97.5321) -> (-63.7009, -67.2297)
  line L20 (-53.2528, -83.9369) -> (-101.7078, -114.2392)
  line L21 (-101.7078, -114.2392) -> (-101.3685, -114.7818)
  arc A22 (-101.3685, -114.7818) -> (-91.7219, -117.0052) centre (-95.4335, -111.0702) ccw
  line L22 (-91.7219, -117.0052) -> (-75.9879, -107.1657)
  arc A23 (-69.38, -105.7298) -> (-75.9879, -107.1657) centre (-70.6856, -115.6442) ccw
  line L23 (-69.38, -105.7298) -> (-36.9537, -110)
  line L24 (36.9063, -110) -> (69.3385, -105.7419)
  arc A24 (75.9473, -107.1813) -> (69.3385, -105.7419) centre (70.6403, -115.6569) ccw
  line L25 (75.9473, -107.1813) -> (91.6749, -117.0292)
  arc A25 (91.6749, -117.0292) -> (101.3228, -114.8112) centre (95.3898, -111.0963) ccw
  line L26 (101.3228, -114.8112) -> (101.6638, -114.2665)
  line L27 (101.6638, -114.2665) -> (53.2259, -83.9369)
  line L28 (63.6871, -67.2297) -> (112.1251, -97.5594)
  line L29 (112.1251, -97.5594) -> (112.4661, -97.0147)
  arc A26 (112.4661, -97.0147) -> (110.2482, -87.3668) centre (106.5332, -93.2997) ccw
  line L30 (110.2482, -87.3668) -> (94.5192, -77.5181)
  arc A27 (90.3391, -72.2039) -> (94.5192, -77.5181) centre (99.8263, -69.0425) ccw
  line L31 (90.3391, -72.2039) -> (80, -41.1773)
  line L32 (80, -41.1773) -> (105.2038, -19.8534)
  arc A28 (111.6628, -17.4876) -> (105.2038, -19.8534) centre (111.6628, -27.4876) ccw
  line L33 (111.6628, -17.4876) -> (130.0112, -17.4876)
  arc A29 (130.0112, -17.4876) -> (137.0099, -10.3502) centre (130.0112, -10.4876) ccw
  line L34 (137.0099, -10.3502) -> (137, -9.8476)
  line L35 (137, -9.8476) -> (80, -9.8476)
  line L36 (80, 9.8574) -> (137, 9.8574)
  line L37 (137, 9.8574) -> (137.0102, 10.3795)
  arc A30 (137.0102, 10.3795) -> (130.0116, 17.5166) centre (130.0116, 10.5166) ccw
  line L38 (130.0116, 17.5166) -> (111.6592, 17.5166)
  arc A31 (105.205, 19.8783) -> (111.6592, 17.5166) centre (111.6592, 27.5166) ccw
  line L39 (105.205, 19.8783) -> (80, 41.1763)
  line L40 (80, 41.1763) -> (90.3206, 72.2298)
  arc A32 (94.5032, 77.5515) -> (90.3206, 72.2298) centre (99.8102, 69.0759) ccw
  line L41 (94.5032, 77.5515) -> (110.2284, 87.3977)
  arc A33 (110.2284, 87.3977) -> (112.4464, 97.0456) centre (106.5135, 93.3307) ccw
  line L42 (112.4464, 97.0456) -> (112.1079, 97.5862)
  line L43 (112.1079, 97.5862) -> (63.6698, 67.2568)
  line L44 (53.2154, 83.9533) -> (101.6535, 114.2827)
  line L45 (101.6535, 114.2827) -> (101.315, 114.8233)
  arc A34 (101.315, 114.8233) -> (91.6672, 117.0413) centre (95.3821, 111.1084) ccw
  line L46 (91.6672, 117.0413) -> (75.938, 107.1925)
  arc A35 (69.3323, 105.7528) -> (75.938, 107.1925) centre (70.631, 115.6682) ccw
  line L47 (69.3323, 105.7528) -> (36.9063, 110)
  line L48 (63.6871, -67.2297) -> (80.6383, -77.8438)
  line L49 (80.6383, -77.8438) -> (70.177, -94.5509)
  line L50 (70.177, -94.5509) -> (53.2259, -83.9369)
  line L51 (53.2259, -83.9369) -> (63.6871, -67.2297)
  line L52 (80, -9.8476) -> (100, -9.8476)
  line L53 (100, -9.8476) -> (100, 9.8574)
  line L54 (100, 9.8574) -> (80, 9.8574)
  line L55 (80, 9.8574) -> (80, -9.8476)
  line L56 (63.6698, 67.2568) -> (80.621, 77.8708)
  line L57 (80.621, 77.8708) -> (70.1666, 94.5673)
  line L58 (70.1666, 94.5673) -> (53.2154, 83.9533)
  line L59 (53.2154, 83.9533) -> (63.6698, 67.2568)
  line L60 (-53.1886, 83.9533) -> (-70.135, 94.5749)
  line L61 (-70.135, 94.5749) -> (-80.5999, 77.8784)
  line L62 (-80.5999, 77.8784) -> (-63.6535, 67.2568)
  line L63 (-63.6535, 67.2568) -> (-53.1886, 83.9533)
  line L64 (-80, -9.8476) -> (-100, -9.8476)
  line L65 (-100, -9.8476) -> (-100, 9.8574)
  line L66 (-100, 9.8574) -> (-80, 9.8574)
  line L67 (-80, 9.8574) -> (-80, -9.8476)
  line L68 (-63.7009, -67.2297) -> (-80.6581, -77.8342)
  line L69 (-80.6581, -77.8342) -> (-70.2099, -94.5413)
  line L70 (-70.2099, -94.5413) -> (-53.2528, -83.9369)
  line L71 (-53.2528, -83.9369) -> (-63.7009, -67.2297)
  line L72 (-53.1886, 83.9533) -> (-63.6535, 67.2568)
  line L73 (53.2259, -83.9369) -> (63.6871, -67.2297)
  line L74 (-63.7009, -67.2297) -> (-53.2528, -83.9369)
  line L75 (-80, 9.8574) -> (-80, -9.8476)
  line L76 (63.6698, 67.2568) -> (53.2154, 83.9533)
  line L77 (80, -9.8476) -> (80, 9.8574)
  circle A36 centre (51.1406, 99.1516) radius 1.85
  circle A37 centre (-51.1844, -99.1397) radius 1.85
  circle A38 centre (-0.0053, -54.0187) radius 1.85
  circle A39 centre (0.0205, 99.5) radius 1.85
  circle A40 centre (51.1462, -99.1427) radius 1.85
  circle A41 centre (-51.1048, 99.1541) radius 1.85
  line L78 (36.9063, 110) -> (-0.5132, 114.9275)
  line L79 (-0.5132, 114.9275) -> (-36.8632, 110)
  line L80 (-36.9537, -110) -> (36.9063, -110)
  dimension "d313" = 20
  dimension "d314" = 20
  dimension "d315" = 20
  dimension "d316" = 20
  dimension "d317" = 20
  dimension "d318" = 20
  constraint coincident L28.start L48.start
  constraint coincident L27 L49.end
  constraint perpendicular L27 L49
  constraint coincident L27.end L50.end
  constraint coincident L35.end L52.start
  constraint coincident L36 L53.end
  constraint perpendicular L36 L53
  constraint coincident L36.start L54.end
  constraint coincident L43.end L56.start
  constraint coincident L43 L56.end
  constraint coincident L44 L57.end
  constraint perpendicular L44 L57
  constraint coincident L44.start L58.end
  constraint coincident L3.end L60.start
  constraint coincident L3 L60.end
  constraint coincident L4 L61.end
  constraint perpendicular L4 L61
  constraint coincident L4.start L62.end
  constraint coincident L12.start L64.start
  constraint coincident L12 L64.end
  constraint coincident L11 L65.end
  constraint perpendicular L11 L65
  constraint coincident L11.end L66.end
  constraint coincident L19.end L68.start
  constraint coincident L19 L68.end
  constraint coincident L20 L69.end
  constraint perpendicular L20 L69
  constraint coincident L20.start L70.end
  measures "d313" distance of L28.start L48.end
  measures "d314" distance of L35.end L52.end
  measures "d315" distance of L43.end L56.end
  measures "d316" distance of L3.end L60.end
  measures "d317" distance of L12.start L64.end
  measures "d318" distance of L19.end L68.end
extrude "Extrude33" add sketch "Sketch22" along normal blind 2 contours L0 A12 L1 A13 L2 L3 L4 L5 A14 L6 A15 L7 L8 A16 L9 A17 L10 L11 L12 L13 A18 L14 A19 L15 L16 A20 L17 A21 L18 L19 L20 L21 A22 L22 A23 L23 L24 A24 L25 A25 L26 L27 L28 L29 A26 L30 A27 L31 L32 A28 L33 A29 L34 L35 L36 L37 A30 L38 A31 L39 L40 A32 L41 A33 L42 L43 L44 L45 A34 L46 A35 L47 L48 L50 L51 L52 L54 L55 L56 L58 L59 L60 L62 L63 L64 L66 L67 L68 L70 L71 L72 L73 L74 L75 L76 L77 L78 L79 L80 | L3 L4 L60 L61 L62 L63 L72 | L43 L44 L56 L57 L58 L59 L76 | L11 L12 L64 L65 L66 L67 L75 | L35 L36 L52 L53 L54 L55 L77 | L19 L20 L68 L69 L70 L71 L74 | L27 L28 L48 L49 L50 L51 L73 | A38 bodies 1
move_body "Move1" bodies 1 to x (-1, 0, 0) y (0, 1, 0) z (0, 0, -1) at (1.2151, 0, 11.8)
move_body "Move2" bodies 1 to x (1, 0, 0) y (0, 1, 0) z (0, 0, 1) at (-1.2628, 0.0169, -13.8)